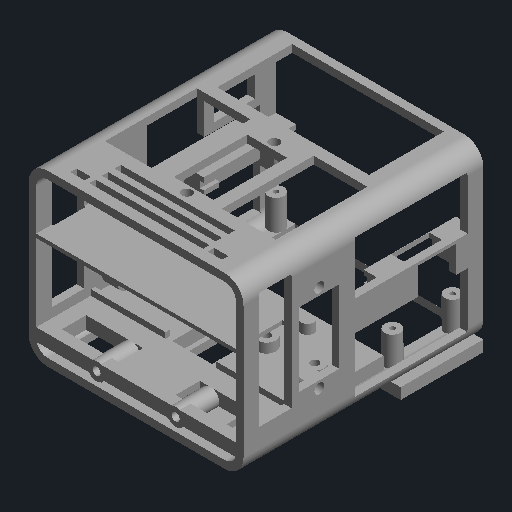
# Autodesk Inventor part: Torso_cuerpo
Saved by Autodesk Inventor 2027 (Build 310192060, 192F)
## iProperties
Part Number: Torso_cuerpo
Material: Genérico
Document SubType Name: Modelado
Designer: rodri
Appearance: Por defecto
Author: rodri
Autodesk Inventor part; units mm, degrees
ref_plane "Plano de trabajo1" through (0, 0, -26.7) normal (0, 0, 1) x (1, 0, 0)
sketch "Boceto1" plane through (0, 0, -26.7) normal (0, 0, 1) x (1, 0, 0)
  line L0 (-34, 4) -> (34, 4)
  line L1 (34, 4) -> (34, 57.7)
  line L2 (34, 57.7) -> (-34, 57.7)
  line L3 (-34, 57.7) -> (-34, 4)
  constraints: 8 end point, 2 parallel, 1 horizontal, 1 perpendicular
extrude "Extrusión1" add sketch "Boceto1" along normal blind 75.9
fillet "Empalme1" radius 6 4 edges at (-34, 4, 11.25) (-34, 57.7, 11.25) (34, 57.7, 11.25) (34, 4, 11.25)
ref_plane "Plano de trabajo2" through (0, 0, -27.7) normal (0, 0, 1) x (1, 0, 0)
sketch "Boceto2" plane through (0, 0, -27.7) normal (0, 0, 1) x (1, 0, 0)
  line L0 (-31.6, 6.4) -> (31.6, 6.4)
  line L1 (31.6, 6.4) -> (31.6, 55.3)
  line L2 (31.6, 55.3) -> (-31.6, 55.3)
  line L3 (-31.6, 55.3) -> (-31.6, 6.4)
  constraints: 8 end point, 2 parallel, 1 horizontal, 1 perpendicular
extrude "Extrusión2" add sketch "Boceto2" along normal blind 77.9 separate body
fillet "Empalme2" radius 3.6 4 edges at (-31.6, 6.4, 11.25) (-31.6, 55.3, 11.25) (31.6, 55.3, 11.25) (31.6, 6.4, 11.25)
combine bodies "Combinar1" operation type subtract main body 1 bodies to subtract 2
ref_plane "Plano de trabajo3" through (0, 0, 2) normal (0, 0, 1) x (1, 0, 0)
sketch "Boceto3" plane through (0, 0, 2) normal (0, 0, 1) x (1, 0, 0)
  line L0 (-31.6, 9) -> (31.6, 9)
  line L1 (31.6, 9) -> (31.6, 13)
  line L2 (31.6, 13) -> (-31.6, 13)
  line L3 (-31.6, 13) -> (-31.6, 9)
  constraints: 8 end point, 2 parallel, 1 horizontal, 1 perpendicular
extrude "Extrusión3" add sketch "Boceto3" along normal blind 47.2 bodies 1
ref_plane "Plano de trabajo4" through (0, 51.3, 0) normal (0, 1, 0) x (-1, 0, 0)
sketch "Boceto4" plane through (0, 51.3, 0) normal (0, 1, 0) x (-1, 0, 0)
  circle A0 centre (0, 5.5) radius 3.25
  circle A1 centre (0, 33.2) radius 3.25
  constraints: 2 centre point
extrude "Extrusión4" add sketch "Boceto4" along normal blind 4.5 bodies 1
ref_plane "Plano de trabajo5" through (26.6, 0, 0) normal (1, 0, 0) x (0, 1, 0)
sketch "Boceto5" plane through (26.6, 0, 0) normal (1, 0, 0) x (0, 1, 0)
  circle A0 centre (17, 25.2) radius 3.25
  circle A1 centre (44.7, 25.2) radius 3.25
  constraints: 2 centre point
extrude "Extrusión5" add sketch "Boceto5" along normal blind 5.5 bodies 1
ref_plane "Plano de trabajo6" through (-32.1, 0, 0) normal (1, 0, 0) x (0, 1, 0)
sketch "Boceto6" plane through (-32.1, 0, 0) normal (1, 0, 0) x (0, 1, 0)
  circle A0 centre (17, 25.2) radius 3.25
  circle A1 centre (44.7, 25.2) radius 3.25
  constraints: 2 centre point
extrude "Extrusión6" add sketch "Boceto6" along normal blind 5.5 bodies 1
ref_plane "Plano de trabajo7" through (0, 0, -26.7) normal (0, 0, 1) x (1, 0, 0)
sketch "Boceto7" plane through (0, 0, -26.7) normal (0, 0, 1) x (1, 0, 0)
  line L0 (25.3, 28.75) -> (31.6, 28.75)
  line L1 (31.6, 28.75) -> (31.6, 33.85)
  line L2 (31.6, 33.85) -> (25.3, 33.85)
  line L3 (25.3, 33.85) -> (25.3, 28.75)
  constraints: 8 end point, 2 parallel, 1 horizontal, 1 perpendicular
extrude "Extrusión7" add sketch "Boceto7" along normal blind 29.2 bodies 1
ref_plane "Plano de trabajo8" through (0, 0, -26.7) normal (0, 0, 1) x (1, 0, 0)
sketch "Boceto8" plane through (0, 0, -26.7) normal (0, 0, 1) x (1, 0, 0)
  line L0 (-31.6, 28.75) -> (-25.3, 28.75)
  line L1 (-25.3, 28.75) -> (-25.3, 33.85)
  line L2 (-25.3, 33.85) -> (-31.6, 33.85)
  line L3 (-31.6, 33.85) -> (-31.6, 28.75)
  constraints: 8 end point, 2 parallel, 1 horizontal, 1 perpendicular
extrude "Extrusión8" add sketch "Boceto8" along normal blind 29.2 bodies 1
ref_plane "Plano de trabajo9" through (0, 0, -26.7) normal (0, 0, 1) x (1, 0, 0)
sketch "Boceto9" plane through (0, 0, -26.7) normal (0, 0, 1) x (1, 0, 0)
  line L0 (25.3, 30.25) -> (26.5, 30.25)
  line L1 (26.5, 30.25) -> (26.5, 32.35)
  line L2 (26.5, 32.35) -> (25.3, 32.35)
  line L3 (25.3, 32.35) -> (25.3, 30.25)
  constraints: 8 end point, 2 parallel, 1 horizontal, 1 perpendicular
extrude "Extrusión9" cut sketch "Boceto9" along normal blind 29.7 bodies 1
ref_plane "Plano de trabajo10" through (0, 0, -21.7) normal (0, 0, 1) x (1, 0, 0)
sketch "Boceto10" plane through (0, 0, -21.7) normal (0, 0, 1) x (1, 0, 0)
  line L0 (25.3, 28.45) -> (26.5, 28.45)
  line L1 (26.5, 28.45) -> (26.5, 30.45)
  line L2 (26.5, 30.45) -> (25.3, 30.45)
  line L3 (25.3, 30.45) -> (25.3, 28.45)
  constraints: 8 end point, 2 parallel, 1 horizontal, 1 perpendicular
extrude "Extrusión10" cut sketch "Boceto10" along normal blind 19.2 bodies 1
ref_plane "Plano de trabajo11" through (0, 0, -26.7) normal (0, 0, 1) x (1, 0, 0)
sketch "Boceto11" plane through (0, 0, -26.7) normal (0, 0, 1) x (1, 0, 0)
  line L0 (-26.5, 30.25) -> (-25.3, 30.25)
  line L1 (-25.3, 30.25) -> (-25.3, 32.35)
  line L2 (-25.3, 32.35) -> (-26.5, 32.35)
  line L3 (-26.5, 32.35) -> (-26.5, 30.25)
  constraints: 8 end point, 2 parallel, 1 horizontal, 1 perpendicular
extrude "Extrusión11" cut sketch "Boceto11" along normal blind 29.7 bodies 1
ref_plane "Plano de trabajo12" through (0, 0, -21.7) normal (0, 0, 1) x (1, 0, 0)
sketch "Boceto12" plane through (0, 0, -21.7) normal (0, 0, 1) x (1, 0, 0)
  line L0 (-26.5, 28.45) -> (-25.3, 28.45)
  line L1 (-25.3, 28.45) -> (-25.3, 30.45)
  line L2 (-25.3, 30.45) -> (-26.5, 30.45)
  line L3 (-26.5, 30.45) -> (-26.5, 28.45)
  constraints: 8 end point, 2 parallel, 1 horizontal, 1 perpendicular
extrude "Extrusión12" cut sketch "Boceto12" along normal blind 19.2 bodies 1
ref_plane "Plano de trabajo13" through (0, 5.9, 0) normal (0, 1, 0) x (-1, 0, 0)
sketch "Boceto13" plane through (0, 5.9, 0) normal (0, 1, 0) x (-1, 0, 0)
  circle A0 centre (-27.94, -23.025) radius 2.5
  circle A1 centre (-27.94, -3.975) radius 2.5
  circle A2 centre (27.94, -23.025) radius 2.5
  circle A3 centre (27.94, -3.975) radius 2.5
  constraints: 4 centre point
extrude "Extrusión13" add sketch "Boceto13" along normal blind 10 bodies 1
ref_plane "Plano de trabajo14" through (0, 0, 30.6) normal (0, 0, 1) x (1, 0, 0)
sketch "Boceto14" plane through (0, 0, 30.6) normal (0, 0, 1) x (1, 0, 0)
  line L0 (8, 12.9) -> (31.6, 12.9)
  line L1 (31.6, 12.9) -> (31.6, 14.8)
  line L2 (31.6, 14.8) -> (8, 14.8)
  line L3 (8, 14.8) -> (8, 12.9)
  constraints: 8 end point, 2 parallel, 1 horizontal, 1 perpendicular
extrude "Extrusión14" add sketch "Boceto14" along normal blind 1.3 bodies 1
ref_plane "Plano de trabajo15" through (0, 0, 30.6) normal (0, 0, 1) x (1, 0, 0)
sketch "Boceto15" plane through (0, 0, 30.6) normal (0, 0, 1) x (1, 0, 0)
  line L0 (-31.6, 12.9) -> (-8, 12.9)
  line L1 (-8, 12.9) -> (-8, 14.8)
  line L2 (-8, 14.8) -> (-31.6, 14.8)
  line L3 (-31.6, 14.8) -> (-31.6, 12.9)
  constraints: 8 end point, 2 parallel, 1 horizontal, 1 perpendicular
extrude "Extrusión15" add sketch "Boceto15" along normal blind 1.3 bodies 1
ref_plane "Plano de trabajo16" through (0, 0, 31.9) normal (0, 0, 1) x (1, 0, 0)
sketch "Boceto16" plane through (0, 0, 31.9) normal (0, 0, 1) x (1, 0, 0)
  line L0 (-31.6, 37.45) -> (31.6, 37.45)
  line L1 (31.6, 37.45) -> (31.6, 38.65)
  line L2 (31.6, 38.65) -> (-31.6, 38.65)
  line L3 (-31.6, 38.65) -> (-31.6, 37.45)
  constraints: 8 end point, 2 parallel, 1 horizontal, 1 perpendicular
extrude "Extrusión16" add sketch "Boceto16" along normal blind 17.3 bodies 1
ref_plane "Plano de trabajo17" through (0, 0, 8.25) normal (0, 0, 1) x (1, 0, 0)
sketch "Boceto17" plane through (0, 0, 8.25) normal (0, 0, 1) x (1, 0, 0)
  line L0 (-6.3, 8.9) -> (6.3, 8.9)
  line L1 (6.3, 8.9) -> (6.3, 13.5)
  line L2 (6.3, 13.5) -> (-6.3, 13.5)
  line L3 (-6.3, 13.5) -> (-6.3, 8.9)
  constraints: 8 end point, 2 parallel, 1 horizontal, 1 perpendicular
extrude "Extrusión17" cut sketch "Boceto17" along normal blind 23.2 bodies 1
ref_plane "Plano de trabajo18" through (0, 0, 3) normal (0, 0, 1) x (1, 0, 0)
sketch "Boceto18" plane through (0, 0, 3) normal (0, 0, 1) x (1, 0, 0)
  line L0 (-7.5, 3.5) -> (7.5, 3.5)
  line L1 (7.5, 3.5) -> (7.5, 6.9)
  line L2 (7.5, 6.9) -> (-7.5, 6.9)
  line L3 (-7.5, 6.9) -> (-7.5, 3.5)
  constraints: 8 end point, 2 parallel, 1 horizontal, 1 perpendicular
extrude "Extrusión18" cut sketch "Boceto18" along normal blind 33.7 bodies 1
ref_plane "Plano de trabajo19" through (0, 8.9, 0) normal (0, 1, 0) x (-1, 0, 0)
sketch "Boceto19" plane through (0, 8.9, 0) normal (0, 1, 0) x (-1, 0, 0)
  circle A0 centre (0, 6) radius 1.6
  circle A1 centre (0, 33.7) radius 1.6
  constraints: 2 centre point
extrude "Extrusión19" cut sketch "Boceto19" along normal blind 3.6 bodies 1
ref_plane "Plano de trabajo20" through (0, 0, 7.75) normal (0, 0, 1) x (1, 0, 0)
sketch "Boceto20" plane through (0, 0, 7.75) normal (0, 0, 1) x (1, 0, 0)
  line L0 (-6.3, 50.3) -> (6.3, 50.3)
  line L1 (6.3, 50.3) -> (6.3, 57.8)
  line L2 (6.3, 57.8) -> (-6.3, 57.8)
  line L3 (-6.3, 57.8) -> (-6.3, 50.3)
  constraints: 8 end point, 2 parallel, 1 horizontal, 1 perpendicular
extrude "Extrusión20" cut sketch "Boceto20" along normal blind 23.2 bodies 1
ref_plane "Plano de trabajo21" through (0, 52.7, 0) normal (0, 1, 0) x (-1, 0, 0)
sketch "Boceto21" plane through (0, 52.7, 0) normal (0, 1, 0) x (-1, 0, 0)
  circle A0 centre (0, 5.5) radius 1.6
  circle A1 centre (0, 33.2) radius 1.6
  constraints: 2 centre point
extrude "Extrusión21" cut sketch "Boceto21" along normal blind 5.1 bodies 1
ref_plane "Plano de trabajo22" through (0, 0, 18.9) normal (0, 0, 1) x (1, 0, 0)
sketch "Boceto22" plane through (0, 0, 18.9) normal (0, 0, 1) x (1, 0, 0)
  line L0 (26.1, 19.25) -> (34.1, 19.25)
  line L1 (34.1, 19.25) -> (34.1, 42.45)
  line L2 (34.1, 42.45) -> (26.1, 42.45)
  line L3 (26.1, 42.45) -> (26.1, 19.25)
  constraints: 8 end point, 2 parallel, 1 horizontal, 1 perpendicular
extrude "Extrusión22" cut sketch "Boceto22" along normal blind 12.6 bodies 1
ref_plane "Plano de trabajo23" through (28, 0, 0) normal (1, 0, 0) x (0, 1, 0)
sketch "Boceto23" plane through (28, 0, 0) normal (1, 0, 0) x (0, 1, 0)
  circle A0 centre (17, 25.2) radius 1.6
  circle A1 centre (44.7, 25.2) radius 1.6
  constraints: 2 centre point
extrude "Extrusión23" cut sketch "Boceto23" along normal blind 6.1 bodies 1
ref_plane "Plano de trabajo24" through (0, 0, 18.9) normal (0, 0, 1) x (1, 0, 0)
sketch "Boceto24" plane through (0, 0, 18.9) normal (0, 0, 1) x (1, 0, 0)
  line L0 (-34.1, 19.25) -> (-26.1, 19.25)
  line L1 (-26.1, 19.25) -> (-26.1, 42.45)
  line L2 (-26.1, 42.45) -> (-34.1, 42.45)
  line L3 (-34.1, 42.45) -> (-34.1, 19.25)
  constraints: 8 end point, 2 parallel, 1 horizontal, 1 perpendicular
extrude "Extrusión24" cut sketch "Boceto24" along normal blind 12.6 bodies 1
ref_plane "Plano de trabajo25" through (-34.1, 0, 0) normal (1, 0, 0) x (0, 1, 0)
sketch "Boceto25" plane through (-34.1, 0, 0) normal (1, 0, 0) x (0, 1, 0)
  circle A0 centre (17, 25.2) radius 1.6
  circle A1 centre (44.7, 25.2) radius 1.6
  constraints: 2 centre point
extrude "Extrusión25" cut sketch "Boceto25" along normal blind 6.1 bodies 1
ref_plane "Plano de trabajo26" through (0, 9.9, 0) normal (0, 1, 0) x (-1, 0, 0)
sketch "Boceto26" plane through (0, 9.9, 0) normal (0, 1, 0) x (-1, 0, 0)
  circle A0 centre (-27.94, -23.025) radius 0.8
  circle A1 centre (-27.94, -3.975) radius 0.8
  circle A2 centre (27.94, -23.025) radius 0.8
  circle A3 centre (27.94, -3.975) radius 0.8
  constraints: 4 centre point
extrude "Extrusión26" cut sketch "Boceto26" along normal blind 6.1 bodies 1
ref_plane "Plano de trabajo27" through (0, 0, -26.8) normal (0, 0, 1) x (1, 0, 0)
sketch "Boceto27" plane through (0, 0, -26.8) normal (0, 0, 1) x (1, 0, 0)
  circle A0 centre (30, 31.3) radius 1.3
  circle A1 centre (-30, 31.3) radius 1.3
  constraints: 2 centre point
extrude "Extrusión27" cut sketch "Boceto27" along normal blind 7.1 bodies 1
ref_plane "Plano de trabajo28" through (0, 0, -18.1) normal (0, 0, 1) x (1, 0, 0)
sketch "Boceto28" plane through (0, 0, -18.1) normal (0, 0, 1) x (1, 0, 0)
  line L0 (25.4, 25.95) -> (34.5, 25.95)
  line L1 (34.5, 25.95) -> (34.5, 35.05)
  line L2 (34.5, 35.05) -> (25.4, 35.05)
  line L3 (25.4, 35.05) -> (25.4, 25.95)
  constraints: 8 end point, 2 parallel, 1 horizontal, 1 perpendicular
extrude "Extrusión28" cut sketch "Boceto28" along normal blind 12 bodies 1
ref_plane "Plano de trabajo29" through (0, 0, -26.69) normal (0, 0, 1) x (1, 0, 0)
sketch "Boceto29" plane through (0, 0, -26.69) normal (0, 0, 1) x (1, 0, 0)
  line L0 (-25.5, 3.5) -> (25.5, 3.5)
  line L1 (25.5, 3.5) -> (25.5, 6.9)
  line L2 (25.5, 6.9) -> (-25.5, 6.9)
  line L3 (-25.5, 6.9) -> (-25.5, 3.5)
  constraints: 8 end point, 2 parallel, 1 horizontal, 1 perpendicular
extrude "Extrusión29" cut sketch "Boceto29" along normal blind 26.19 bodies 1
ref_plane "Plano de trabajo30" through (0, 0, -24.2) normal (0, 0, 1) x (1, 0, 0)
sketch "Boceto30" plane through (0, 0, -24.2) normal (0, 0, 1) x (1, 0, 0)
  line L0 (-24, 54.8) -> (24, 54.8)
  line L1 (24, 54.8) -> (24, 58.2)
  line L2 (24, 58.2) -> (-24, 58.2)
  line L3 (-24, 58.2) -> (-24, 54.8)
  constraints: 8 end point, 2 parallel, 1 horizontal, 1 perpendicular
extrude "Extrusión30" cut sketch "Boceto30" along normal blind 23.7 bodies 1
ref_plane "Plano de trabajo31" through (0, 0, -21.7) normal (0, 0, 1) x (1, 0, 0)
sketch "Boceto31" plane through (0, 0, -21.7) normal (0, 0, 1) x (1, 0, 0)
  line L0 (31.1, 9) -> (34.5, 9)
  line L1 (34.5, 9) -> (34.5, 26.5)
  line L2 (34.5, 26.5) -> (31.1, 26.5)
  line L3 (31.1, 26.5) -> (31.1, 9)
  constraints: 8 end point, 2 parallel, 1 horizontal, 1 perpendicular
extrude "Extrusión31" cut sketch "Boceto31" along normal blind 35.7 bodies 1
ref_plane "Plano de trabajo32" through (0, 0, -21.7) normal (0, 0, 1) x (1, 0, 0)
sketch "Boceto32" plane through (0, 0, -21.7) normal (0, 0, 1) x (1, 0, 0)
  line L0 (31.1, 36) -> (34.5, 36)
  line L1 (34.5, 36) -> (34.5, 52.7)
  line L2 (34.5, 52.7) -> (31.1, 52.7)
  line L3 (31.1, 52.7) -> (31.1, 36)
  constraints: 8 end point, 2 parallel, 1 horizontal, 1 perpendicular
extrude "Extrusión32" cut sketch "Boceto32" along normal blind 35.7 bodies 1
ref_plane "Plano de trabajo33" through (0, 0, 34) normal (0, 0, 1) x (1, 0, 0)
sketch "Boceto33" plane through (0, 0, 34) normal (0, 0, 1) x (1, 0, 0)
  line L0 (31.1, 16) -> (34.5, 16)
  line L1 (34.5, 16) -> (34.5, 52.7)
  line L2 (34.5, 52.7) -> (31.1, 52.7)
  line L3 (31.1, 52.7) -> (31.1, 16)
  constraints: 8 end point, 2 parallel, 1 horizontal, 1 perpendicular
extrude "Extrusión33" cut sketch "Boceto33" along normal blind 10.2 bodies 1
ref_plane "Plano de trabajo34" through (0, 0, -21.7) normal (0, 0, 1) x (1, 0, 0)
sketch "Boceto34" plane through (0, 0, -21.7) normal (0, 0, 1) x (1, 0, 0)
  line L0 (-34.5, 9) -> (-31.1, 9)
  line L1 (-31.1, 9) -> (-31.1, 26.5)
  line L2 (-31.1, 26.5) -> (-34.5, 26.5)
  line L3 (-34.5, 26.5) -> (-34.5, 9)
  constraints: 8 end point, 2 parallel, 1 horizontal, 1 perpendicular
extrude "Extrusión34" cut sketch "Boceto34" along normal blind 35.7 bodies 1
ref_plane "Plano de trabajo35" through (0, 0, -21.7) normal (0, 0, 1) x (1, 0, 0)
sketch "Boceto35" plane through (0, 0, -21.7) normal (0, 0, 1) x (1, 0, 0)
  line L0 (-34.5, 36) -> (-31.1, 36)
  line L1 (-31.1, 36) -> (-31.1, 52.7)
  line L2 (-31.1, 52.7) -> (-34.5, 52.7)
  line L3 (-34.5, 52.7) -> (-34.5, 36)
  constraints: 8 end point, 2 parallel, 1 horizontal, 1 perpendicular
extrude "Extrusión35" cut sketch "Boceto35" along normal blind 35.7 bodies 1
ref_plane "Plano de trabajo36" through (0, 0, 34) normal (0, 0, 1) x (1, 0, 0)
sketch "Boceto36" plane through (0, 0, 34) normal (0, 0, 1) x (1, 0, 0)
  line L0 (-34.5, 16) -> (-31.1, 16)
  line L1 (-31.1, 16) -> (-31.1, 52.7)
  line L2 (-31.1, 52.7) -> (-34.5, 52.7)
  line L3 (-34.5, 52.7) -> (-34.5, 16)
  constraints: 8 end point, 2 parallel, 1 horizontal, 1 perpendicular
extrude "Extrusión36" cut sketch "Boceto36" along normal blind 10.2 bodies 1
ref_plane "Plano de trabajo37" through (0, 0, 3) normal (0, 0, 1) x (1, 0, 0)
sketch "Boceto37" plane through (0, 0, 3) normal (0, 0, 1) x (1, 0, 0)
  line L0 (10, 54.8) -> (27, 54.8)
  line L1 (27, 54.8) -> (27, 58.2)
  line L2 (27, 58.2) -> (10, 58.2)
  line L3 (10, 58.2) -> (10, 54.8)
  constraints: 8 end point, 2 parallel, 1 horizontal, 1 perpendicular
extrude "Extrusión37" cut sketch "Boceto37" along normal blind 29 bodies 1
ref_plane "Plano de trabajo38" through (0, 0, 3) normal (0, 0, 1) x (1, 0, 0)
sketch "Boceto38" plane through (0, 0, 3) normal (0, 0, 1) x (1, 0, 0)
  line L0 (-27, 54.8) -> (-10, 54.8)
  line L1 (-10, 54.8) -> (-10, 58.2)
  line L2 (-10, 58.2) -> (-27, 58.2)
  line L3 (-27, 58.2) -> (-27, 54.8)
  constraints: 8 end point, 2 parallel, 1 horizontal, 1 perpendicular
extrude "Extrusión38" cut sketch "Boceto38" along normal blind 29 bodies 1
ref_plane "Plano de trabajo39" through (0, 0, 1) normal (0, 0, 1) x (1, 0, 0)
sketch "Boceto39" plane through (0, 0, 1) normal (0, 0, 1) x (1, 0, 0)
  line L0 (18.5, 3.5) -> (28, 3.5)
  line L1 (28, 3.5) -> (28, 6.9)
  line L2 (28, 6.9) -> (18.5, 6.9)
  line L3 (18.5, 6.9) -> (18.5, 3.5)
  constraints: 8 end point, 2 parallel, 1 horizontal, 1 perpendicular
extrude "Extrusión39" cut sketch "Boceto39" along normal blind 43.2 bodies 1
ref_plane "Plano de trabajo40" through (0, 0, 1) normal (0, 0, 1) x (1, 0, 0)
sketch "Boceto40" plane through (0, 0, 1) normal (0, 0, 1) x (1, 0, 0)
  line L0 (-28, 3.5) -> (-18.5, 3.5)
  line L1 (-18.5, 3.5) -> (-18.5, 6.9)
  line L2 (-18.5, 6.9) -> (-28, 6.9)
  line L3 (-28, 6.9) -> (-28, 3.5)
  constraints: 8 end point, 2 parallel, 1 horizontal, 1 perpendicular
extrude "Extrusión40" cut sketch "Boceto40" along normal blind 43.2 bodies 1
ref_plane "Plano de trabajo41" through (0, 0, 1) normal (0, 0, 1) x (1, 0, 0)
sketch "Boceto41" plane through (0, 0, 1) normal (0, 0, 1) x (1, 0, 0)
  line L0 (-18.5, 3.5) -> (18.5, 3.5)
  line L1 (18.5, 3.5) -> (18.5, 6.9)
  line L2 (18.5, 6.9) -> (-18.5, 6.9)
  line L3 (-18.5, 6.9) -> (-18.5, 3.5)
  constraints: 8 end point, 2 parallel, 1 horizontal, 1 perpendicular
extrude "Extrusión41" cut sketch "Boceto41" along normal blind 5.7 bodies 1
ref_plane "Plano de trabajo42" through (0, 0, 38) normal (0, 0, 1) x (1, 0, 0)
sketch "Boceto42" plane through (0, 0, 38) normal (0, 0, 1) x (1, 0, 0)
  line L0 (9, 8.5) -> (27, 8.5)
  line L1 (27, 8.5) -> (27, 13.5)
  line L2 (27, 13.5) -> (9, 13.5)
  line L3 (9, 13.5) -> (9, 8.5)
  constraints: 8 end point, 2 parallel, 1 horizontal, 1 perpendicular
extrude "Extrusión42" cut sketch "Boceto42" along normal blind 7.68 bodies 1
ref_plane "Plano de trabajo43" through (0, 0, 38) normal (0, 0, 1) x (1, 0, 0)
sketch "Boceto43" plane through (0, 0, 38) normal (0, 0, 1) x (1, 0, 0)
  line L0 (-27, 8.5) -> (-9, 8.5)
  line L1 (-9, 8.5) -> (-9, 13.5)
  line L2 (-9, 13.5) -> (-27, 13.5)
  line L3 (-27, 13.5) -> (-27, 8.5)
  constraints: 8 end point, 2 parallel, 1 horizontal, 1 perpendicular
extrude "Extrusión43" cut sketch "Boceto43" along normal blind 7.68 bodies 1
ref_plane "Plano de trabajo44" through (0, 0, 38.2) normal (0, 0, 1) x (1, 0, 0)
sketch "Boceto44" plane through (0, 0, 38.2) normal (0, 0, 1) x (1, 0, 0)
  circle A0 centre (12.5, 10.5) radius 2.8
  circle A1 centre (-12.5, 10.5) radius 2.8
  constraints: 2 centre point
extrude "Extrusión44" add sketch "Boceto44" along normal blind 11 bodies 1
ref_plane "Plano de trabajo45" through (0, 0, 38.7) normal (0, 0, 1) x (1, 0, 0)
sketch "Boceto45" plane through (0, 0, 38.7) normal (0, 0, 1) x (1, 0, 0)
  circle A0 centre (12.5, 10.5) radius 1.3
  circle A1 centre (-12.5, 10.5) radius 1.3
  constraints: 2 centre point
extrude "Extrusión45" cut sketch "Boceto45" along normal blind 10.6 bodies 1
ref_plane "Plano de trabajo46" through (0, 0, 44) normal (0, 0, 1) x (1, 0, 0)
sketch "Boceto46" plane through (0, 0, 44) normal (0, 0, 1) x (1, 0, 0)
  line L0 (19.5, 54.8) -> (24, 54.8)
  line L1 (24, 54.8) -> (24, 58.2)
  line L2 (24, 58.2) -> (19.5, 58.2)
  line L3 (19.5, 58.2) -> (19.5, 54.8)
  constraints: 8 end point, 2 parallel, 1 horizontal, 1 perpendicular
extrude "Extrusión46" cut sketch "Boceto46" along normal blind 2 bodies 1
ref_plane "Plano de trabajo47" through (0, 0, 44) normal (0, 0, 1) x (1, 0, 0)
sketch "Boceto47" plane through (0, 0, 44) normal (0, 0, 1) x (1, 0, 0)
  line L0 (-24, 54.8) -> (-19.5, 54.8)
  line L1 (-19.5, 54.8) -> (-19.5, 58.2)
  line L2 (-19.5, 58.2) -> (-24, 58.2)
  line L3 (-24, 58.2) -> (-24, 54.8)
  constraints: 8 end point, 2 parallel, 1 horizontal, 1 perpendicular
extrude "Extrusión47" cut sketch "Boceto47" along normal blind 2 bodies 1
ref_plane "Plano de trabajo48" through (0, 0, -23) normal (0, 0, 1) x (1, 0, 0)
sketch "Boceto48" plane through (0, 0, -23) normal (0, 0, 1) x (1, 0, 0)
  line L0 (-34, 38.5) -> (-31.61, 38.5)
  line L1 (-31.61, 38.5) -> (-31.61, 50)
  line L2 (-31.61, 50) -> (-34, 50)
  line L3 (-34, 50) -> (-34, 38.5)
  constraints: 8 end point, 2 parallel, 1 horizontal, 1 perpendicular
extrude "Extrusión48" add sketch "Boceto48" along normal blind 19 bodies 1
ref_plane "Plano de trabajo49" through (0, 0, -20) normal (0, 0, 1) x (1, 0, 0)
sketch "Boceto49" plane through (0, 0, -20) normal (0, 0, 1) x (1, 0, 0)
  line L0 (-34.5, 41) -> (-31.1, 41)
  line L1 (-31.1, 41) -> (-31.1, 49.5)
  line L2 (-31.1, 49.5) -> (-34.5, 49.5)
  line L3 (-34.5, 49.5) -> (-34.5, 41)
  constraints: 8 end point, 2 parallel, 1 horizontal, 1 perpendicular
extrude "Extrusión49" cut sketch "Boceto49" along normal blind 13 bodies 1
ref_plane "Plano de trabajo50" through (0, 0, 36) normal (0, 0, 1) x (1, 0, 0)
sketch "Boceto50" plane through (0, 0, 36) normal (0, 0, 1) x (1, 0, 0)
  line L0 (-18, 54.8) -> (18, 54.8)
  line L1 (18, 54.8) -> (18, 58.2)
  line L2 (18, 58.2) -> (-18, 58.2)
  line L3 (-18, 58.2) -> (-18, 54.8)
  constraints: 8 end point, 2 parallel, 1 horizontal, 1 perpendicular
extrude "Extrusión50" cut sketch "Boceto50" along normal blind 2 bodies 1
ref_plane "Plano de trabajo51" through (0, 0, 40) normal (0, 0, 1) x (1, 0, 0)
sketch "Boceto51" plane through (0, 0, 40) normal (0, 0, 1) x (1, 0, 0)
  line L0 (-18, 54.8) -> (18, 54.8)
  line L1 (18, 54.8) -> (18, 58.2)
  line L2 (18, 58.2) -> (-18, 58.2)
  line L3 (-18, 58.2) -> (-18, 54.8)
  constraints: 8 end point, 2 parallel, 1 horizontal, 1 perpendicular
extrude "Extrusión51" cut sketch "Boceto51" along normal blind 2 bodies 1
ref_plane "Plano de trabajo52" through (0, 0, 44) normal (0, 0, 1) x (1, 0, 0)
sketch "Boceto52" plane through (0, 0, 44) normal (0, 0, 1) x (1, 0, 0)
  line L0 (-18, 54.8) -> (18, 54.8)
  line L1 (18, 54.8) -> (18, 58.2)
  line L2 (18, 58.2) -> (-18, 58.2)
  line L3 (-18, 58.2) -> (-18, 54.8)
  constraints: 8 end point, 2 parallel, 1 horizontal, 1 perpendicular
extrude "Extrusión52" cut sketch "Boceto52" along normal blind 2 bodies 1
ref_plane "Plano de trabajo53" through (0, 4.5, 0) normal (0, 1, 0) x (-1, 0, 0)
sketch "Boceto53" plane through (0, 4.5, 0) normal (0, 1, 0) x (-1, 0, 0)
  circle A0 centre (-12.5, 32.2) radius 3
  circle A1 centre (12.5, 32.2) radius 3
  circle A2 centre (-10, 15.2) radius 3
  circle A3 centre (10, 15.2) radius 3
  constraints: 4 centre point
extrude "Extrusión53" add sketch "Boceto53" along normal blind 4.6 bodies 1
ref_plane "Plano de trabajo54" through (0, 3.9, 0) normal (0, 1, 0) x (-1, 0, 0)
sketch "Boceto54" plane through (0, 3.9, 0) normal (0, 1, 0) x (-1, 0, 0)
  circle A0 centre (-12.5, 32.2) radius 1.3
  circle A1 centre (12.5, 32.2) radius 1.3
  circle A2 centre (-10, 15.2) radius 1.3
  circle A3 centre (10, 15.2) radius 1.3
  constraints: 4 centre point
extrude "Extrusión54" cut sketch "Boceto54" along normal blind 7.6 bodies 1
ref_plane "Plano de trabajo55" through (0, 0, -26.7) normal (0, 0, 1) x (1, 0, 0)
sketch "Boceto55" plane through (0, 0, -26.7) normal (0, 0, 1) x (1, 0, 0)
  line L0 (26, 1) -> (34, 1)
  line L1 (34, 1) -> (34, 4.5)
  line L2 (34, 4.5) -> (26, 4.5)
  line L3 (26, 4.5) -> (26, 1)
  constraints: 8 end point, 2 parallel, 1 horizontal, 1 perpendicular
extrude "Extrusión55" add sketch "Boceto55" along normal blind 26.2 bodies 1
ref_plane "Plano de trabajo56" through (0, 0, -26.7) normal (0, 0, 1) x (1, 0, 0)
sketch "Boceto56" plane through (0, 0, -26.7) normal (0, 0, 1) x (1, 0, 0)
  line L0 (-34, 1) -> (-26, 1)
  line L1 (-26, 1) -> (-26, 4.5)
  line L2 (-26, 4.5) -> (-34, 4.5)
  line L3 (-34, 4.5) -> (-34, 1)
  constraints: 8 end point, 2 parallel, 1 horizontal, 1 perpendicular
extrude "Extrusión56" add sketch "Boceto56" along normal blind 26.2 bodies 1
ref_plane "Plano de trabajo57" through (0, 12.9, 0) normal (0, 1, 0) x (-1, 0, 0)
sketch "Boceto57" plane through (0, 12.9, 0) normal (0, 1, 0) x (-1, 0, 0)
  circle A0 centre (-9.98, 17.9) radius 3
  circle A1 centre (-25.22, 17.9) radius 3
  constraints: 2 centre point
extrude "Extrusión57" add sketch "Boceto57" along normal blind 3.1 bodies 1
ref_plane "Plano de trabajo58" through (0, 12.9, 0) normal (0, 1, 0) x (-1, 0, 0)
sketch "Boceto58" plane through (0, 12.9, 0) normal (0, 1, 0) x (-1, 0, 0)
  circle A0 centre (-12, 7) radius 2
  circle A1 centre (-24, 7) radius 2
  constraints: 2 centre point
extrude "Extrusión58" add sketch "Boceto58" along normal blind 3.1 bodies 1
ref_plane "Plano de trabajo59" through (0, 10.5, 0) normal (0, 1, 0) x (-1, 0, 0)
sketch "Boceto59" plane through (0, 10.5, 0) normal (0, 1, 0) x (-1, 0, 0)
  circle A0 centre (-9.98, 17.9) radius 1.3
  circle A1 centre (-25.22, 17.9) radius 1.3
  constraints: 2 centre point
extrude "Extrusión59" cut sketch "Boceto59" along normal blind 5.6 bodies 1
ref_plane "Plano de trabajo60" through (0, 4, 25.2) normal (0, 1, 0) x (0, 0, 1)
ref_plane "Plano de trabajo61" through (0, 4, 25.2) normal (1, 0, 0) x (0, 0, -1)
ref_plane "Plano de trabajo62" through (0, 26, 19.85) normal (0, 1, 0) x (0, 0, 1)
ref_plane "Plano de trabajo63" through (0, 26, 19.85) normal (1, 0, 0) x (0, 0, -1)
ref_plane "Plano de trabajo64" through (0, 40.7, 19.35) normal (0, 1, 0) x (0, 0, 1)
ref_plane "Plano de trabajo65" through (0, 40.7, 19.35) normal (1, 0, 0) x (0, 0, -1)
ref_plane "Plano de trabajo66" through (17, 30.85, 25.2) normal (0, 1, 0) x (0, 0, 1)
ref_plane "Plano de trabajo67" through (17, 30.85, 25.2) normal (1, 0, 0) x (0, 0, -1)
ref_plane "Plano de trabajo68" through (-17, 30.85, 25.2) normal (0, 1, 0) x (0, 0, 1)
ref_plane "Plano de trabajo69" through (-17, 30.85, 25.2) normal (1, 0, 0) x (0, 0, -1)
ref_plane "Plano de trabajo70" through (-29.21, 17.5, -19.7) normal (0, 1, 0) x (0, 0, 1)
ref_plane "Plano de trabajo71" through (-29.21, 17.5, -19.7) normal (1, 0, 0) x (0, 0, -1)
ref_plane "Plano de trabajo72" through (23.37, 30.45, -24.17) normal (0, 1, 0) x (0, 0, 1)
ref_plane "Plano de trabajo73" through (23.37, 30.45, -24.17) normal (1, 0, 0) x (0, 0, -1)
ref_plane "Plano de trabajo74" through (-31, 13.5, 32) normal (0, 1, 0) x (0, 0, 1)
ref_plane "Plano de trabajo75" through (-31, 13.5, 32) normal (1, 0, 0) x (0, 0, -1)
ref_plane "Plano de trabajo76" through (-26.15, 38.75, 31.8) normal (0, 1, 0) x (0, 0, 1)
ref_plane "Plano de trabajo77" through (-26.15, 38.75, 31.8) normal (1, 0, 0) x (0, 0, -1)
ref_plane "Plano de trabajo78" through (-25.4, -6.5, -26) normal (0, 1, 0) x (0, 0, 1)
ref_plane "Plano de trabajo79" through (-25.4, -6.5, -26) normal (1, 0, 0) x (0, 0, -1)
ref_plane "Plano de trabajo80" through (-19.1, 34.55, -26.2) normal (0, 1, 0) x (0, 0, 1)
ref_plane "Plano de trabajo81" through (-19.1, 34.55, -26.2) normal (1, 0, 0) x (0, 0, -1)
ref_plane "Plano de trabajo82" through (-19.1, 34.55, -0.6) normal (0, 1, 0) x (0, 0, 1)
ref_plane "Plano de trabajo83" through (-19.1, 34.55, -0.6) normal (1, 0, 0) x (0, 0, -1)
ref_plane "Plano de trabajo84" through (7, 16, 4) normal (0, 1, 0) x (0, 0, 1)
ref_plane "Plano de trabajo85" through (7, 16, 4) normal (1, 0, 0) x (0, 0, -1)
ref_plane "Plano de trabajo86" through (7.45, 17.6, 4.3) normal (0, 1, 0) x (0, 0, 1)
ref_plane "Plano de trabajo87" through (7.45, 17.6, 4.3) normal (1, 0, 0) x (0, 0, -1)
ref_plane "Plano de trabajo88" through (0, 0, 0) normal (0, 1, 0) x (0, 0, 1)
ref_plane "Plano de trabajo89" through (0, 0, 0) normal (1, 0, 0) x (0, 0, -1)
